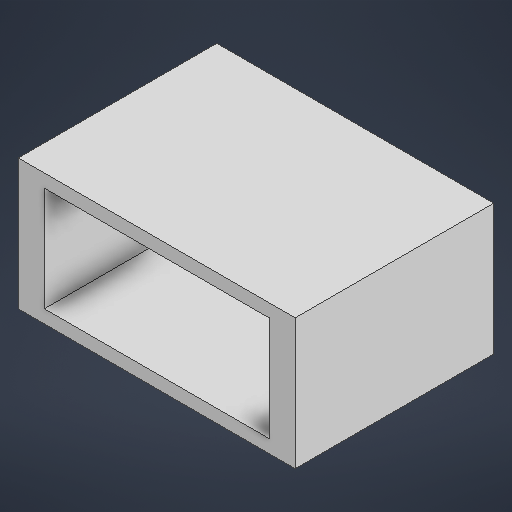
# Autodesk Inventor part: NOWYSERWO
Saved by Autodesk Inventor 2026.1 (Build 301233020, 233B)
## iProperties
Created: 2026-09-21
Part Number: NOWYSERWO
Material: Ogólny
Document SubType Name: Modeling
Designer: Bronh
Density: 1 g/cm^3
Appearance: Domyślna
Author: Bronh
Autodesk Inventor part; units mm, degrees
ref_plane "YZ Plane" through (0, 0, 0) normal (1, 0, 0) x (0, 1, 0)
ref_plane "XZ Plane" through (0, 0, 0) normal (0, 1, 0) x (-1, 0, 0)
ref_plane "XY Plane" through (0, 0, 0) normal (0, 0, 1) x (1, 0, 0)
sketch "Szkic1" plane through (0, 0, 0) normal (0, 0, 1) x (1, 0, 0)
  line L0 (0, 0) -> (53, 0)
  line L1 (53, 0) -> (53, 25)
  line L2 (53, 25) -> (0, 25)
  line L3 (0, 25) -> (0, 0)
  dimension "d0" = 53
  dimension "d1" = 25
  constraints: 8 end point, 2 parallel, 1 horizontal, 1 perpendicular
  measures "d0" distance of L2.end L1.end
  measures "d1" distance of L1.end L0.end
extrude "Wyciągnięcie proste1" add sketch "Szkic1" along normal blind 38
sketch "Szkic2" plane through (0, 0, 38) normal (0, 0, 1) x (1, 0, 0)
  line L0 (5, 22.5) -> (48, 22.5)
  line L1 (48, 22.5) -> (48, 2.5)
  line L2 (48, 2.5) -> (5, 2.5)
  line L3 (5, 2.5) -> (5, 22.5)
  line L4 (0, 25) -> (0, 0) projected
  line L5 (53, 25) -> (0, 25) projected
  dimension "d4" = 43
  dimension "d5" = 20
  dimension "d6" = 5
  dimension "d7" = 2.5
  constraints: 8 end point, 2 parallel, 1 horizontal, 1 perpendicular
  measures "d4" distance of L1.end L2.end
  measures "d5" distance of L0.end L1.end
  measures "d6" distance between parallel lines of L4 L3
  measures "d7" distance between parallel lines of L0 L5
extrude "Wyciągnięcie proste2" cut sketch "Szkic2" against normal blind 28
sketch "Szkic3" plane through (0, 0, 0) normal (-1, 0, 0) x (0, 0, 1)
  line L0 (19, 17.5) -> (10, 17.5)
  line L1 (10, 17.5) -> (10, 7.5)
  line L2 (10, 7.5) -> (19, 7.5)
  line L3 (19, 7.5) -> (19, 17.5)
  line L4 (0, 25) -> (0, 0) projected
  line L5 (38, 2.5) -> (10, 2.5) projected
  point P0 (10, 12.5)
  dimension "d10" = 9
  dimension "d11" = 10
  dimension "d12" = 10
  dimension "d13" = 5
  constraints: 8 end point, 2 parallel, 1 horizontal, 1 midpoint, 1 perpendicular
  measures "d10" distance of L2.end L1.end
  measures "d11" distance of L1.end L0.end
  measures "d12" distance from line of L4 point (10, 12.5)
  measures "d13" distance between parallel lines of L5 L2
extrude "Wyciągnięcie proste3" cut sketch "Szkic3" against normal blind 6
